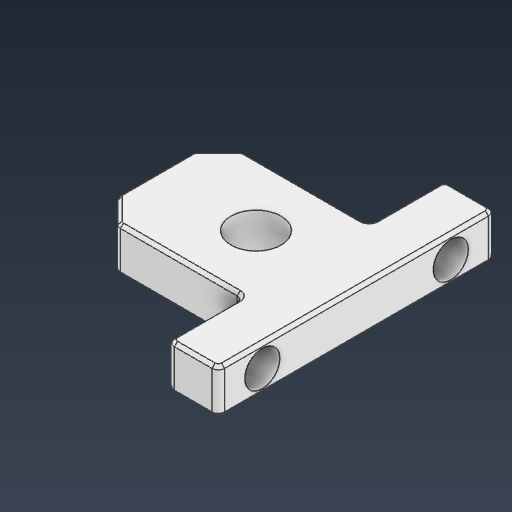
# Autodesk Inventor part: z-axis bearing puller support
Saved by Autodesk Inventor 2026.2 (Build 302298010, 298A)
## iProperties
Created: 2026-04-26
Part Number: z-axis bearing puller support
Material: ABS 플라스틱
Document SubType Name: Modeling
Designer: work
Density: 1.06 g/cm^3
Appearance: 매끄러움 - 흰색
Mass: 0.652771 g
Surface Area: 7.03991 cm^2
Volume: 0.615822 cm^3
Author: work
Autodesk Inventor part; units mm, degrees
ref_plane "YZ Plane" through (0, 0, 0) normal (1, 0, 0) x (0, 1, 0)
ref_plane "XZ Plane" through (0, 0, 0) normal (0, 1, 0) x (-1, 0, 0)
ref_plane "XY Plane" through (0, 0, 0) normal (0, 0, 1) x (1, 0, 0)
sketch "스케치1" plane through (0, 0, 0) normal (0, 1, 0) x (-1, 0, 0)
  circle A0 centre (0, 0) radius 2
  line L0 (0, 0) -> (-8, 0)
  line L1 (8, 5) -> (-8, 5)
  line L2 (-8, 5) -> (-8, -5)
  line L3 (-8, -5) -> (8, -5)
  line L4 (8, -5) -> (8, 5)
  line L5 (8, 5) -> (-8, -5) construction
  line L6 (-8, 5) -> (8, -5) construction
  line L7 (-8, 5) -> (-4, 5)
  line L8 (-4, 5) -> (-4, 11)
  line L9 (-4, 11) -> (-8, 11)
  line L10 (-8, 11) -> (-8, 5)
  line L11 (-8, -5) -> (-4, -5)
  line L12 (-4, -5) -> (-4, -11)
  line L13 (-4, -11) -> (-8, -11)
  line L14 (-8, -11) -> (-8, -5)
  point P0 (-4, -5)
  point P1 (-4, 5)
  dimension "d0" = 4
  dimension "d1" = 8
  dimension "d2" = 16
  dimension "d3" = 10
  dimension "d4" = 4
  dimension "d5" = 6
  dimension "d6" = 4
  dimension "d7" = 6
  constraints: 30 end point, 6 parallel, 4 horizontal, 3 perpendicular, 2 midpoint, 1 centre point, 1 coincident
  measures "d0" diameter of A0
  measures "d1" distance of L0.start L0.end
  measures "d2" distance of L3.end L2.end
  measures "d3" distance of L2.end L1.end
  measures "d4" distance of L9.end L8.end
  measures "d5" distance of L8.end L7.end
  measures "d6" distance of L12.end L13.end
  measures "d7" distance of L11.end L12.end
extrude "돌출1" add sketch "스케치1" along normal blind 3.5
sketch "스케치2" plane through (4, 0, 5) normal (-1, 0, 0) x (0, 0, 1)
  line L0 (-5, 0) -> (-5, 3.5) construction
  line L1 (6, 3.5) -> (-16, 3.5) projected
  line L2 (-12.5, 1.75) -> (2.5, 1.75) construction
  circle A0 centre (-12.5, 1.75) radius 1.4
  circle A1 centre (2.5, 1.75) radius 1.4
  point P0 (-5, 1.75)
  dimension "d10" = 15
  dimension "d11" = 2.8
  dimension "d12" = 2.8
  constraints: 4 end point, 3 midpoint, 2 centre point, 2 coincident, 1 horizontal
  measures "d10" distance of L2.start L2.end
  measures "d11" diameter of A0
  measures "d12" diameter of A1
extrude "돌출2" cut sketch "스케치2" against normal through all
chamfer "모따기1" distance 2 angle 45 2 edges at (-8, 1.75, -5) (-8, 1.75, 5)
fillet "모깎기1" radius 0.5 10 edges at (4, 1.75, -11) (8, 1.75, -11) (8, 1.75, 11) (4, 1.75, 11) (-6, 1.75, 5) (-8, 1.75, 3) (4, 1.75, 5) (4, 1.75, -5) (-6, 1.75, -5) (-8, 1.75, -3)
chamfer "모따기2" distance 0.25 angle 45 40 edges at (-7, 3.5, -4) (-5.9842, 3.5, -4.9619) (-1.1464, 3.5, -5) (3.8536, 3.5, -5.1464) (4, 3.5, -8) (4.1464, 3.5, -10.8536) (6, 3.5, -11) (7.8536, 3.5, -10.8536) (8, 3.5, 0) (7.8536, 3.5, 10.8536) (6, 3.5, 11) (4.1464, 3.5, 10.8536) (4, 3.5, 8) (3.8536, 3.5, 5.1464) (-1.1464, 3.5, 5) (-5.9842, 3.5, 4.9619) (-7, 3.5, 4) (-7.9619, 3.5, 2.9842) (-8, 3.5, 0) (-7.9619, 3.5, -2.9842) (-8, 0, 0) (-7.9619, 0, 2.9842) (-7, 0, 4) (-5.9842, 0, 4.9619) (-1.1464, 0, 5) (3.8536, 0, 5.1464) (4, 0, 8) (4.1464, 0, 10.8536) (6, 0, 11) (7.8536, 0, 10.8536) (8, 0, 0) (7.8536, 0, -10.8536) (6, 0, -11) (4.1464, 0, -10.8536) (4, 0, -8) (3.8536, 0, -5.1464) (-1.1464, 0, -5) (-5.9842, 0, -4.9619) (-7, 0, -4) (-7.9619, 0, -2.9842)
